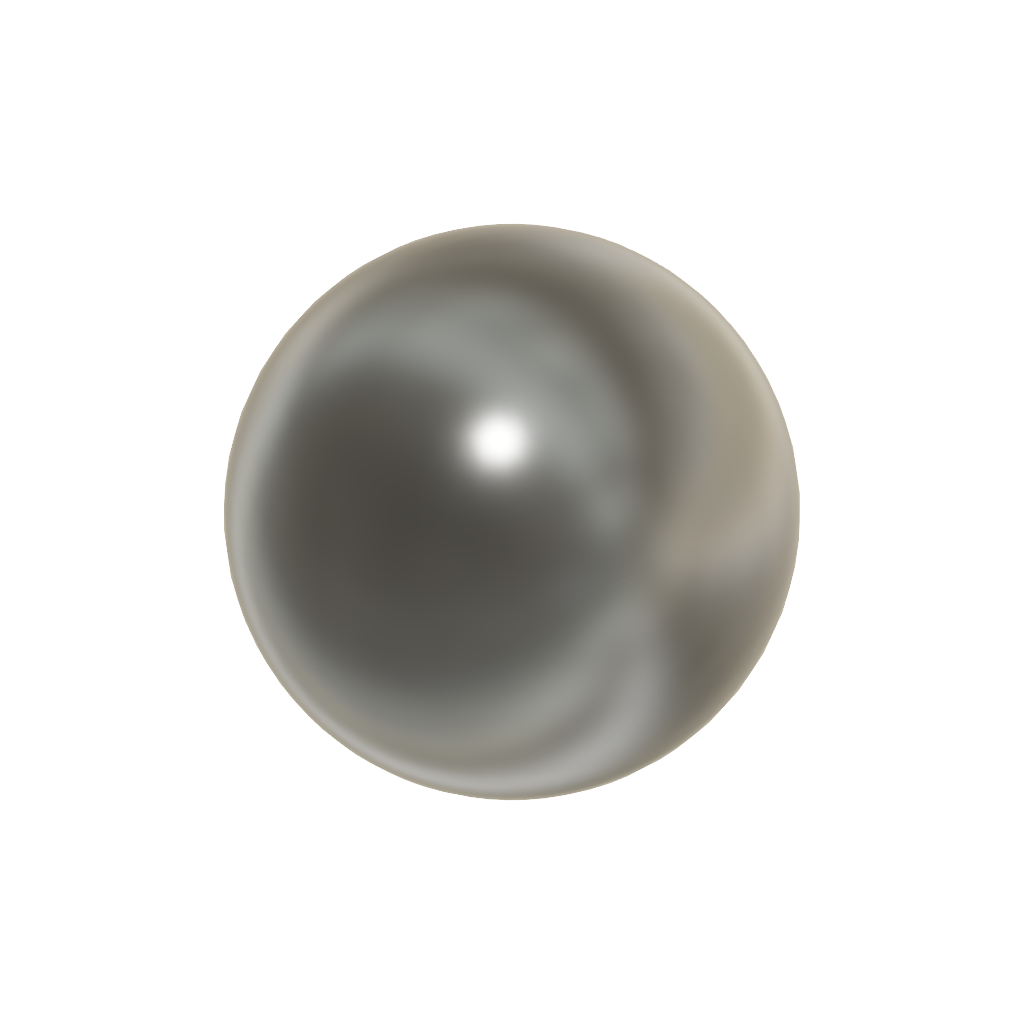
Marble ( Plain ) (Autodesk Fusion 360 design; units mm, degrees)
part number: 2026-10-18-19-34-22-836
Autodesk Fusion 360 part; units mm, degrees
sketch "Sketch1" plane through (0, 0, 0) normal (0, 1, 0) x (1, 0, 0)
  line L0 (0, -7.5) -> (0, 7.5)
  arc A0 (0, -7.5) -> (0, 7.5) centre (0, 0) ccw
  constraint coincident A0.centre origin
  constraint perpendicular L0 A0
revolve "Revolve1" add sketch "Sketch1" angle 360 about axis through (0, 0, 7.5) along (0, 0, -1)
